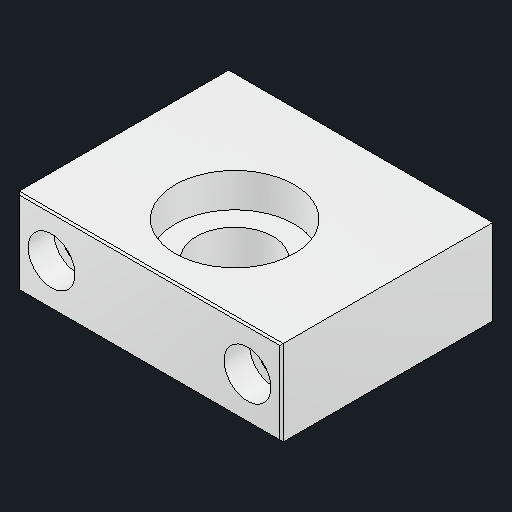
# Autodesk Inventor part: monotaro-thrust-support-block
Saved by Autodesk Inventor 2027.1 (Build 311270010, 270A)
## iProperties
Created: 2026-11-06
Part Number: monotaro-thrust-support-block
Material: Aluminum 6061
Description: Concept: opposed uncovered 6001 bearing stop block; nominal seat, mounting and endplay to finalize
Document SubType Name: Modeling
Designer: queezz
Density: 2.7 g/cm^3
Appearance: Aluminum - Flat
Author: queezz
Autodesk Inventor part; units mm, degrees
ref_plane "Block footprint plane" through (0, 0, 0) normal (0, 0, 1) x (1, 0, 0)
sketch "Block footprint" plane through (0, 0, 0) normal (0, 0, 1) x (1, 0, 0)
  line L0 (-31, 0) -> (31, 0)
  line L1 (31, 0) -> (31, 20)
  line L2 (31, 20) -> (-31, 20)
  line L3 (-31, 20) -> (-31, 0)
  point P0 (0, 0)
  dimension "d0" = 62
  dimension "d1" = 20
  constraints: 8 end point, 2 parallel, 1 horizontal, 1 midpoint, 1 perpendicular
  measures "d0" distance of L0.start L0.end
  measures "d1" distance of L0.end L1.end
extrude "Block blank" add sketch "Block footprint" along normal blind 50
ref_plane "Bearing seat plane" through (0, 20, 30) normal (0, -1, 0) x (1, 0, 0)
sketch "Bearing seat" plane through (0, 20, 30) normal (0, -1, 0) x (1, 0, 0)
  circle A0 centre (0, 0) radius 14
  dimension "d4" = 28
  constraints: 1 centre point, 1 other
  measures "d4" diameter of A0
extrude "Open 6001 seat" cut sketch "Bearing seat" along normal blind 8
ref_plane "Shaft clearance plane" through (0, 20, 30) normal (0, -1, 0) x (1, 0, 0)
sketch "Shaft clearance" plane through (0, 20, 30) normal (0, -1, 0) x (1, 0, 0)
  circle A0 centre (0, 0) radius 9
  dimension "d7" = 18
  constraints: 1 centre point, 1 other
  measures "d7" diameter of A0
extrude "Through shaft opening" cut sketch "Shaft clearance" along normal blind 20
ref_plane "Mounting holes plane" through (0, 0, 50) normal (0, 0, 1) x (1, 0, 0)
sketch "Mounting holes" plane through (0, 0, 50) normal (0, 0, 1) x (1, 0, 0)
  circle A0 centre (-23, 10) radius 3.3
  circle A1 centre (23, 10) radius 3.3
  dimension "d10" = 6.6
  dimension "d11" = 6.6
  constraints: 2 centre point, 2 other
  measures "d10" diameter of A0
  measures "d11" diameter of A1
extrude "Two M6 clearance holes" cut sketch "Mounting holes" against normal blind 50
ref_plane "Bolt head pockets plane" through (0, 0, 50) normal (0, 0, 1) x (1, 0, 0)
sketch "Bolt head pockets" plane through (0, 0, 50) normal (0, 0, 1) x (1, 0, 0)
  circle A0 centre (-23, 10) radius 5.5
  circle A1 centre (23, 10) radius 5.5
  dimension "d14" = 11
  dimension "d15" = 11
  constraints: 2 centre point, 2 other
  measures "d14" diameter of A0
  measures "d15" diameter of A1
extrude "Two bolt head counterbores" cut sketch "Bolt head pockets" against normal blind 6
sketch "Sketch6" plane through (0, 0, 0) normal (0, 1, 0) x (-1, 0, 0)
  circle A0 centre (0, 30) radius 13.1
  constraints: 1 centre point
extrude "Outside 51101 housing washer register" [suppressed]
sketch "Sketch7" plane through (0, 0, 0) normal (0, 1, 0) x (-1, 0, 0)
  circle A0 centre (0, 30) radius 13.1
  constraints: 1 centre point
extrude "Outside 51101 register 26.2 x 1.5" cut sketch "Sketch7" along normal blind 1.5
chamfer "C0.4 outside perimeter" distance 0.4 angle 45 8 edges at (-31, 10, 0) (-31, 10, 50) (0, 20, 0) (0, 20, 50) (31, 10, 0) (31, 10, 50) (0, 0, 0) (0, 0, 50)
equation "\"d0\" = block_width"
equation "\"d1\" = block_depth"
equation "\"d2\" = block_height"
equation "\"d4\" = bearing_seat_diameter"
equation "\"d5\" = bearing_seat_depth"
equation "\"d7\" = shaft_clearance"
equation "\"d8\" = block_depth"
equation "\"d10\" = mounting_clearance"
equation "\"d11\" = mounting_clearance"
equation "\"d12\" = block_height"
equation "\"d14\" = head_counterbore"
equation "\"d15\" = head_counterbore"
equation "\"d16\" = head_recess"
equation "\"block_width\" = 62"
equation "\"block_depth\" = 20"
equation "\"block_height\" = 50"
equation "\"bearing_seat_diameter\" = 28"
equation "\"bearing_seat_depth\" = 8"
equation "\"shaft_clearance\" = 18"
equation "\"mounting_clearance\" = 6.6"
equation "\"head_counterbore\" = 11"
equation "\"head_recess\" = 6"
body "Solid1"
